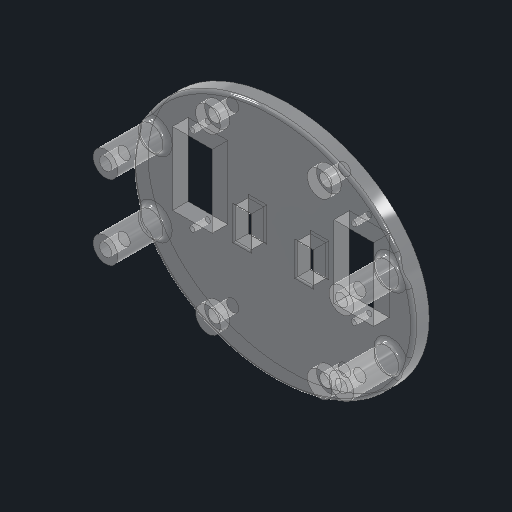
# Autodesk Inventor part: PEN-001
Saved by Autodesk Inventor 2027.1 (Build 311270010, 270A)
## iProperties
Created: 2026-10-28
Part Number: PEN-001
Material: PETG 3D Print
Description: Base plate, PETG
Document SubType Name: Modeling
Designer: shyan
Mass: 33.2722 g
Surface Area: 140.109 cm^2
Volume: 26.1986 cm^3
Density: 1.27 g/cm^3
Appearance: Polycarbonate - Clear
Author: shyan
Autodesk Inventor part; units mm, degrees
sketch "sk_plate" plane through (0, 0, 0) normal (0, 0, 1) x (1, 0, 0)
  line L0 (0, 0) -> (60, 0) construction
  line L1 (0, 0) -> (0, 60) construction
  ellipse E0 centre (0, 0) end of major axis (45.3, 0) minor radius 37.3
  dimension "d0" = 45.3
  dimension "d1" = 37.3
  constraints: 4 end point, 2 point on line, 1 centre point, 5 other
extrude "Plate" add sketch "sk_plate" along normal blind 5
sketch "sk_hip_pocket" plane through (0, 0, 0) normal (0, 0, 1) x (1, 0, 0)
  line L0 (0, 0) -> (60, 0) construction
  line L1 (0, 0) -> (0, 60) construction
  line L2 (19.6, -6.2) -> (32.4, -6.2)
  line L3 (32.4, -6.2) -> (32.4, 17.2)
  line L4 (32.4, 17.2) -> (19.6, 17.2)
  line L5 (19.6, 17.2) -> (19.6, -6.2)
  circle A0 centre (26, 19.25) radius 0.85
  circle A1 centre (26, -8.25) radius 0.85
  dimension "d4" = 12.8
  dimension "d5" = 23.4
  dimension "d6" = 19.6
  dimension "d7" = 6.2
  dimension "d8" = 1.7
  dimension "d9" = 26
  dimension "d10" = 19.25
  dimension "d11" = 1.7
  dimension "d12" = 26
  dimension "d13" = 8.25
  constraints: 12 end point, 2 centre point, 2 parallel, 1 horizontal, 1 perpendicular, 4 other
  measures "d4" distance of L2.start L2.end
  measures "d5" distance of L2.end L3.end
  measures "d6" horizontal distance of L0.start L4.end
  measures "d7" vertical distance of L0.start L2.start
  measures "d8" diameter of A0
  measures "d9" horizontal distance of L0.start A0.centre
  measures "d10" vertical distance of L0.start A0.centre
  measures "d11" diameter of A1
  measures "d12" horizontal distance of L0.start A1.centre
  measures "d13" vertical distance of L0.start A1.centre
extrude "HipPocket_R" cut sketch "sk_hip_pocket" along normal through all
mirror "HipPocket_L" about plane through (0, 0, 0) normal (1, 0, 0) of "HipPocket_R"
sketch "sk_cable_slots" plane through (0, 0, 0) normal (0, 0, 1) x (1, 0, 0)
  line L0 (0, 0) -> (60, 0) construction
  line L1 (0, 0) -> (0, 60) construction
  line L2 (7.5, -5) -> (12.5, -5)
  line L3 (12.5, -5) -> (12.5, 5)
  line L4 (12.5, 5) -> (7.5, 5)
  line L5 (7.5, 5) -> (7.5, -5)
  line L6 (-12.5, -5) -> (-7.5, -5)
  line L7 (-7.5, -5) -> (-7.5, 5)
  line L8 (-7.5, 5) -> (-12.5, 5)
  line L9 (-12.5, 5) -> (-12.5, -5)
  dimension "d16" = 5
  dimension "d17" = 10
  dimension "d18" = 7.5
  dimension "d19" = 5
  dimension "d20" = 10
  dimension "d21" = 12.5
  constraints: 20 end point, 4 parallel, 2 horizontal, 2 perpendicular, 6 other
  measures "d16" distance of L2.start L2.end
  measures "d17" distance of L2.end L3.end
  measures "d18" horizontal distance of L0.start L4.end
  measures "d19" distance of L6.start L6.end
  measures "d20" distance of L6.end L7.end
  measures "d21" horizontal distance of L0.start L8.end
extrude "CableSlots" cut sketch "sk_cable_slots" along normal through all
ref_plane "sk_columns_plane" through (0, 0, 5) normal (0, 0, 1) x (1, 0, 0)
sketch "sk_columns" plane through (0, 0, 5) normal (0, 0, 1) x (1, 0, 0)
  line L0 (0, 0) -> (60, 0) construction
  line L1 (0, 0) -> (0, 60) construction
  circle A0 centre (38, 12) radius 4
  circle A1 centre (-38, 12) radius 4
  circle A2 centre (38, -12) radius 4
  circle A3 centre (-38, -12) radius 4
  dimension "d25" = 8
  dimension "d26" = 38
  dimension "d27" = 12
  dimension "d28" = 8
  dimension "d29" = 38
  dimension "d30" = 12
  dimension "d31" = 8
  dimension "d32" = 38
  dimension "d33" = 12
  dimension "d34" = 8
  dimension "d35" = 38
  dimension "d36" = 12
  constraints: 4 centre point, 4 end point, 4 other
  measures "d25" diameter of A0
  measures "d26" horizontal distance of L0.start A0.centre
  measures "d27" vertical distance of L0.start A0.centre
  measures "d28" diameter of A1
  measures "d29" horizontal distance of L0.start A1.centre
  measures "d30" vertical distance of L0.start A1.centre
  measures "d31" diameter of A2
  measures "d32" horizontal distance of L0.start A2.centre
  measures "d33" vertical distance of L0.start A2.centre
  measures "d34" diameter of A3
  measures "d35" horizontal distance of L0.start A3.centre
  measures "d36" vertical distance of L0.start A3.centre
extrude "Columns" add sketch "sk_columns" along normal blind 16
ref_plane "sk_bosses_plane" through (0, 0, 5) normal (0, 0, 1) x (1, 0, 0)
sketch "sk_bosses" plane through (0, 0, 5) normal (0, 0, 1) x (1, 0, 0)
  line L0 (0, 0) -> (60, 0) construction
  line L1 (0, 0) -> (0, 60) construction
  circle A0 centre (18, 28) radius 4
  circle A1 centre (-18, 28) radius 4
  circle A2 centre (18, -28) radius 4
  circle A3 centre (-18, -28) radius 4
  dimension "d40" = 8
  dimension "d41" = 18
  dimension "d42" = 28
  dimension "d43" = 8
  dimension "d44" = 18
  dimension "d45" = 28
  dimension "d46" = 8
  dimension "d47" = 18
  dimension "d48" = 28
  dimension "d49" = 8
  dimension "d50" = 18
  dimension "d51" = 28
  constraints: 4 centre point, 4 end point, 4 other
  measures "d40" diameter of A0
  measures "d41" horizontal distance of L0.start A0.centre
  measures "d42" vertical distance of L0.start A0.centre
  measures "d43" diameter of A1
  measures "d44" horizontal distance of L0.start A1.centre
  measures "d45" vertical distance of L0.start A1.centre
  measures "d46" diameter of A2
  measures "d47" horizontal distance of L0.start A2.centre
  measures "d48" vertical distance of L0.start A2.centre
  measures "d49" diameter of A3
  measures "d50" horizontal distance of L0.start A3.centre
  measures "d51" vertical distance of L0.start A3.centre
extrude "ShellBosses" add sketch "sk_bosses" along normal blind 3
ref_plane "sk_col_inserts_plane" through (0, 0, 21) normal (0, 0, 1) x (1, 0, 0)
sketch "sk_col_inserts" plane through (0, 0, 21) normal (0, 0, 1) x (1, 0, 0)
  line L0 (0, 0) -> (60, 0) construction
  line L1 (0, 0) -> (0, 60) construction
  circle A0 centre (38, 12) radius 2
  circle A1 centre (-38, 12) radius 2
  circle A2 centre (38, -12) radius 2
  circle A3 centre (-38, -12) radius 2
  dimension "d55" = 4
  dimension "d56" = 38
  dimension "d57" = 12
  dimension "d58" = 4
  dimension "d59" = 38
  dimension "d60" = 12
  dimension "d61" = 4
  dimension "d62" = 38
  dimension "d63" = 12
  dimension "d64" = 4
  dimension "d65" = 38
  dimension "d66" = 12
  constraints: 4 centre point, 4 end point, 4 other
  measures "d55" diameter of A0
  measures "d56" horizontal distance of L0.start A0.centre
  measures "d57" vertical distance of L0.start A0.centre
  measures "d58" diameter of A1
  measures "d59" horizontal distance of L0.start A1.centre
  measures "d60" vertical distance of L0.start A1.centre
  measures "d61" diameter of A2
  measures "d62" horizontal distance of L0.start A2.centre
  measures "d63" vertical distance of L0.start A2.centre
  measures "d64" diameter of A3
  measures "d65" horizontal distance of L0.start A3.centre
  measures "d66" vertical distance of L0.start A3.centre
extrude "ColumnInserts" cut sketch "sk_col_inserts" against normal blind 6
sketch "sk_boss_inserts" plane through (0, 0, 0) normal (0, 0, 1) x (1, 0, 0)
  line L0 (0, 0) -> (60, 0) construction
  line L1 (0, 0) -> (0, 60) construction
  circle A0 centre (18, 28) radius 2
  circle A1 centre (-18, 28) radius 2
  circle A2 centre (18, -28) radius 2
  circle A3 centre (-18, -28) radius 2
  dimension "d69" = 4
  dimension "d70" = 18
  dimension "d71" = 28
  dimension "d72" = 4
  dimension "d73" = 18
  dimension "d74" = 28
  dimension "d75" = 4
  dimension "d76" = 18
  dimension "d77" = 28
  dimension "d78" = 4
  dimension "d79" = 18
  dimension "d80" = 28
  constraints: 4 centre point, 4 end point, 4 other
  measures "d69" diameter of A0
  measures "d70" horizontal distance of L0.start A0.centre
  measures "d71" vertical distance of L0.start A0.centre
  measures "d72" diameter of A1
  measures "d73" horizontal distance of L0.start A1.centre
  measures "d74" vertical distance of L0.start A1.centre
  measures "d75" diameter of A2
  measures "d76" horizontal distance of L0.start A2.centre
  measures "d77" vertical distance of L0.start A2.centre
  measures "d78" diameter of A3
  measures "d79" horizontal distance of L0.start A3.centre
  measures "d80" vertical distance of L0.start A3.centre
extrude "BossInserts" cut sketch "sk_boss_inserts" along normal blind 6
fillet "FilletColumnRoots" radius 1.5 4 edges at (34, -12, 5) (34, 12, 5) (-42, 12, 5) (-42, -12, 5)
fillet "FilletSlots" radius 0.5 16 edges at (7.5, 0, 5) (10, 5, 5) (12.5, 0, 5) (10, -5, 5) (-12.5, 0, 5) (-10, 5, 5) (-7.5, 0, 5) (-10, -5, 5) (12.5, 0, 0) (10, -5, 0) (7.5, 0, 0) (10, 5, 0) (-7.5, 0, 0) (-10, -5, 0) (-12.5, 0, 0) (-10, 5, 0)
fillet "FilletTopRim" radius 1 5 edges at (0, 37.3, 5) (-45.3, 0, 5) (0, -37.3, 5) (44.8135, -5.4518, 5) (44.8135, 5.4518, 5)
ref_plane "pl_hipX_R" through (26, 0, 0) normal (1, 0, 0) x (0, 1, 0)
ref_plane "pl_hipX_L" through (-26, 0, 0) normal (1, 0, 0) x (0, 1, 0)
equation "\"d0\" = -clr + 0.5 * bodyW0 - wall"
equation "\"d1\" = -clr + 0.5 * bodyD0 - wall"
equation "\"d2\" = plate_T"
equation "\"d4\" = sv_W + 2 * clr"
equation "\"d5\" = sv_L + 2 * clr"
equation "\"d6\" = hip_x - 0.5 * sv_W - clr"
equation "\"d7\" = sv_shaft + clr"
equation "\"d8\" = m2_pilot"
equation "\"d9\" = hip_x"
equation "\"d10\" = -sv_shaft + 0.5 * sv_L + 0.5 * sv_pitch"
equation "\"d11\" = m2_pilot"
equation "\"d12\" = hip_x"
equation "\"d13\" = -0.5 * sv_L + 0.5 * sv_pitch + sv_shaft"
equation "\"d16\" = slot_W"
equation "\"d17\" = slot_L"
equation "\"d18\" = slot_x - 0.5 * slot_W"
equation "\"d19\" = slot_W"
equation "\"d20\" = slot_L"
equation "\"d21\" = slot_x + 0.5 * slot_W"
equation "\"d25\" = col_d"
equation "\"d26\" = col_x"
equation "\"d27\" = col_y"
equation "\"d28\" = col_d"
equation "\"d29\" = col_x"
equation "\"d30\" = col_y"
equation "\"d31\" = col_d"
equation "\"d32\" = col_x"
equation "\"d33\" = col_y"
equation "\"d34\" = col_d"
equation "\"d35\" = col_x"
equation "\"d36\" = col_y"
equation "\"d37\" = col_H"
equation "\"d40\" = boss_d"
equation "\"d41\" = boss_x"
equation "\"d42\" = boss_y"
equation "\"d43\" = boss_d"
equation "\"d44\" = boss_x"
equation "\"d45\" = boss_y"
equation "\"d46\" = boss_d"
equation "\"d47\" = boss_x"
equation "\"d48\" = boss_y"
equation "\"d49\" = boss_d"
equation "\"d50\" = boss_x"
equation "\"d51\" = boss_y"
equation "\"d52\" = boss_h"
equation "\"d55\" = ins_d"
equation "\"d56\" = col_x"
equation "\"d57\" = col_y"
equation "\"d58\" = ins_d"
equation "\"d59\" = col_x"
equation "\"d60\" = col_y"
equation "\"d61\" = ins_d"
equation "\"d62\" = col_x"
equation "\"d63\" = col_y"
equation "\"d64\" = ins_d"
equation "\"d65\" = col_x"
equation "\"d66\" = col_y"
equation "\"d67\" = ins_L"
equation "\"d69\" = ins_d"
equation "\"d70\" = boss_x"
equation "\"d71\" = boss_y"
equation "\"d72\" = ins_d"
equation "\"d73\" = boss_x"
equation "\"d74\" = boss_y"
equation "\"d75\" = ins_d"
equation "\"d76\" = boss_x"
equation "\"d77\" = boss_y"
equation "\"d78\" = ins_d"
equation "\"d79\" = boss_x"
equation "\"d80\" = boss_y"
equation "\"d81\" = ins_L"
equation "\"d83\" = fil_col"
equation "\"d84\" = fil_slot"
equation "\"d85\" = fil_top"
equation "\"clr\" = 0.3"
equation "\"wall\" = 2.4"
equation "\"sv_L\" = 22.8"
equation "\"sv_W\" = 12.2"
equation "\"sv_H\" = 22.7"
equation "\"sv_full\" = 28.5"
equation "\"sv_tab\" = 32.5"
equation "\"sv_tabT\" = 2.5"
equation "\"sv_tabZ\" = 15.5"
equation "\"sv_pitch\" = 27.5"
equation "\"sv_shaft\" = 5.9"
equation "\"sv_dome\" = 12"
equation "\"sv_domeH\" = 3.3"
equation "\"sv_spline\" = 4.8"
equation "\"m2_pilot\" = 1.7"
equation "\"horn_len\" = 31.5"
equation "\"horn_hub\" = 7.2"
equation "\"horn_tip\" = 4.5"
equation "\"horn_T\" = 1.8"
equation "\"horn_hubH\" = 3.8"
equation "\"ins_d\" = 4"
equation "\"ins_L\" = 6"
equation "\"m3\" = 3.4"
equation "\"nut_af\" = 5.8"
equation "\"hip_x\" = 26"
equation "\"plate_T\" = 5"
equation "\"col_H\" = 16"
equation "\"tray_T\" = 3"
equation "\"bodyW0\" = 96"
equation "\"bodyW35\" = 106"
equation "\"bodyD35\" = 86"
equation "\"bodyW85\" = 92"
equation "\"bodyD85\" = 74"
equation "\"bodyW112\" = 64"
equation "\"bodyD112\" = 56"
equation "\"Z_sec1\" = 35"
equation "\"Z_sec2\" = 85"
equation "\"Z_sec3\" = 112"
equation "\"Z_flip\" = 78"
equation "\"Z_bridge\" = 98"
equation "\"bat_W\" = 77"
equation "\"bat_D\" = 41"
equation "\"bat_H\" = 21"
equation "\"esp_W\" = 55"
equation "\"esp_D\" = 28"
equation "\"esp_H\" = 13"
equation "\"pcb_D\" = 38"
equation "\"pcb_T\" = 1.6"
equation "\"bk_D\" = 22"
equation "\"df_W\" = 49"
equation "\"df_D\" = 32"
equation "\"df_H\" = 12"
equation "\"sw_W\" = 21"
equation "\"sw_D\" = 15"
equation "\"sw_H\" = 25"
equation "\"usb_cut_W\" = 12"
equation "\"usb_cut_H\" = 7"
equation "\"usb_pitch\" = 28"
equation "\"slot_W\" = 5"
equation "\"slot_L\" = 10"
equation "\"col_d\" = 8"
equation "\"col_x\" = 38"
equation "\"col_y\" = 12"
equation "\"boss_d\" = 8"
equation "\"boss_h\" = 3"
equation "\"boss_x\" = 18"
equation "\"boss_y\" = 28"
equation "\"fil_top\" = 1"
equation "\"fil_col\" = 1.5"
equation "\"fil_slot\" = 0.5"
equation "\"d24\" = plate_T"
equation "\"d39\" = plate_T"
equation "\"d54\" = plate_T + col_H"
equation "\"d86\" = hip_x"
equation "\"d87\" = -hip_x"
equation "\"bodyD0\" = 80"
equation "\"slot_x\" = 10"
body "Solid1"
